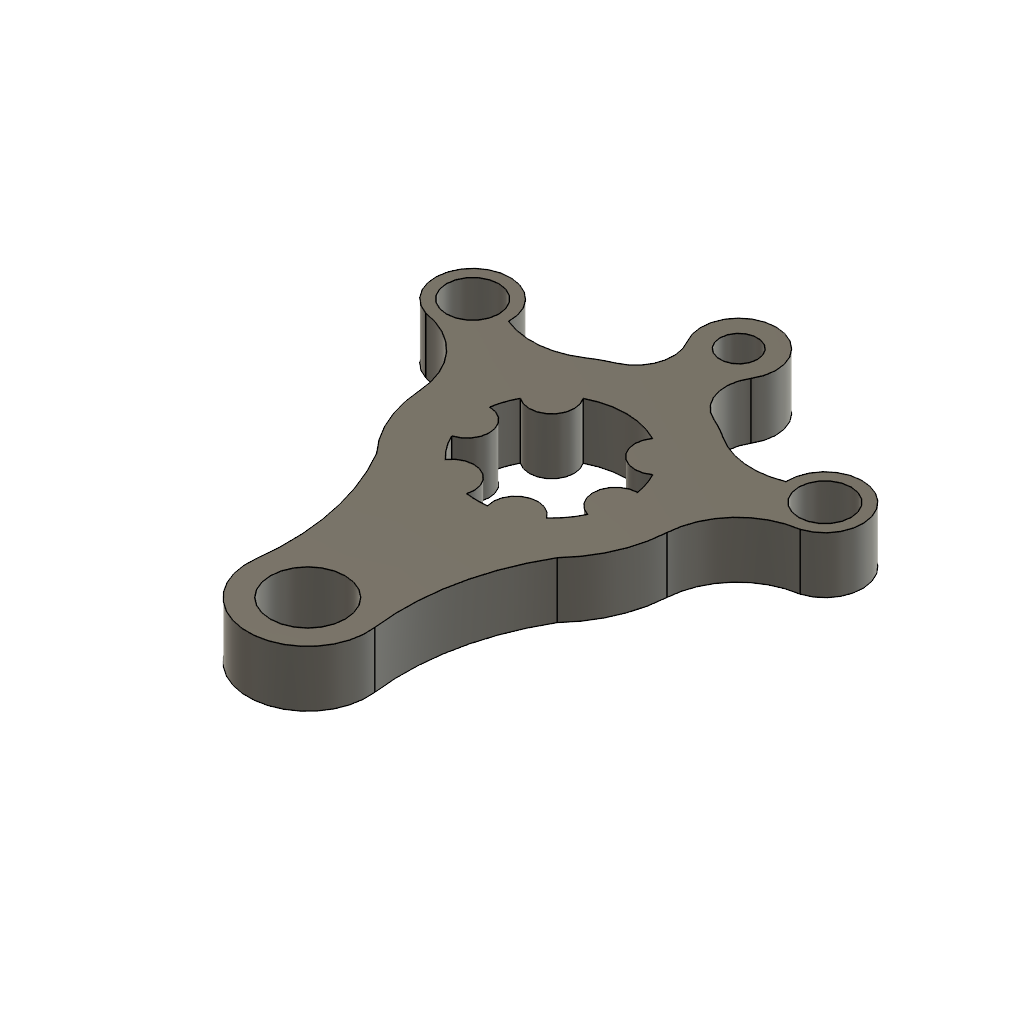
ex 1.1 (Autodesk Fusion 360 design; units mm, degrees)
part number: 2026-10-05-16-02-38-002
Autodesk Fusion 360 part; units mm, degrees
sketch "Sketch1" plane through (0, 0, 0) normal (0, 1, 0) x (1, 0, 0)
  line L0 (0, 0) -> (0, -65)
  line L1 (0, 0) -> (0, 50)
  line L2 (0, 50) -> (-47, 50)
  circle A0 centre (-47, 26) radius 7
  circle A1 centre (0, -65) radius 10
  circle A2 centre (0, 50) radius 5
  arc A3 (-13.0587, 30.3063) -> (-9.5135, 46.1017) centre (-17.0159, 39.49) ccw
  arc A4 (-37.0085, 25.5888) -> (-18.3132, 27.4523) centre (-29.4121, 44.09) ccw
  arc A5 (-9.5135, 46.1017) -> (-10.3052, 50) centre (-29.4121, 44.09) ccw
  arc A6 (-13.0587, 30.3063) -> (-18.3132, 27.4523) centre (0, 0) ccw
  arc A7 (-2.778, -19.8061) -> (-13.5097, -14.7474) centre (-8.5276, -18.0909) ccw
  arc A8 (-18.1189, -8.4679) -> (-13.5097, -14.7474) centre (0, 0) ccw
  arc A9 (-18.1189, -8.4679) -> (-19.7281, 3.2867) centre (-19.8152, -2.7127) ccw
  arc A10 (-17.6648, 9.3783) -> (-19.7281, 3.2867) centre (0, 0) ccw
  arc A11 (-17.6648, 9.3783) -> (-9.2437, 17.7357) centre (-14.0883, 14.1958) ccw
  arc A12 (-32.9346, -2.0764) -> (-49.9628, 16.449) centre (-52.895, -3.3349) ccw
  arc A13 (-15.8705, -62.9687) -> (-24.1042, -22.5385) centre (-79.3527, -54.8435) ccw
  circle A14 centre (0, -65) radius 10
  arc A15 (24.1042, -22.5385) -> (15.8705, -62.9687) centre (79.3527, -54.8435) ccw
  arc A16 (19.7281, 3.2867) -> (18.1189, -8.4679) centre (19.8152, -2.7127) ccw
  arc A17 (13.5097, -14.7474) -> (18.1189, -8.4679) centre (0, 0) ccw
  arc A18 (9.2437, 17.7357) -> (17.6648, 9.3783) centre (14.0883, 14.1958) ccw
  arc A19 (9.5135, 46.1017) -> (13.0587, 30.3063) centre (17.0159, 39.49) ccw
  arc A20 (18.3132, 27.4523) -> (13.0587, 30.3063) centre (0, 0) ccw
  arc A21 (18.3132, 27.4523) -> (37.0085, 25.5888) centre (29.4121, 44.09) ccw
  circle A22 centre (47, 26) radius 7
  arc A23 (49.9628, 16.449) -> (32.9346, -2.0764) centre (52.895, -3.3349) ccw
  arc A24 (-15.8705, -62.9687) -> (15.8705, -62.9687) centre (0, -65) ccw
  arc A25 (-15.8705, -62.9687) -> (15.8705, -62.9687) centre (0, -65) ccw
  arc A26 (8.5079, 44.745) -> (-8.5079, 44.745) centre (0, 50) ccw
  arc A27 (47.9568, 16.0459) -> (37.0085, 25.5888) centre (47, 26) ccw
  arc A28 (-37.0085, 25.5888) -> (-47.9568, 16.0459) centre (-47, 26) ccw
  arc A29 (13.5097, -14.7474) -> (2.778, -19.8061) centre (8.5276, -18.0909) ccw
  line L3 (0, 0) -> (0, -65)
  arc A30 (-2.778, -19.8061) -> (2.778, -19.8061) centre (0, 0) ccw
  arc A31 (-2.778, -19.8061) -> (2.778, -19.8061) centre (0, 0) ccw
  arc A32 (13.5097, -14.7474) -> (18.1189, -8.4679) centre (0, 0) ccw
  arc A33 (19.7281, 3.2867) -> (17.6648, 9.3783) centre (0, 0) ccw
  arc A34 (9.2437, 17.7357) -> (-9.2437, 17.7357) centre (0, 0) ccw
  arc A35 (9.2437, 17.7357) -> (-9.2437, 17.7357) centre (0, 0) ccw
  arc A36 (-17.6648, 9.3783) -> (-19.7281, 3.2867) centre (0, 0) ccw
  arc A37 (-18.1189, -8.4679) -> (-13.5097, -14.7474) centre (0, 0) ccw
  arc A38 (8.5079, 44.745) -> (-8.5079, 44.745) centre (0, 50) ccw
  arc A39 (29.6039, -14.5811) -> (32.9346, -2.0764) centre (0, 0) ccw
  arc A40 (-32.9346, -2.0764) -> (-24.1042, -22.5385) centre (0, 0) ccw
  arc A41 (24.1042, -22.5385) -> (32.9346, -2.0764) centre (0, 0) ccw
  arc A42 (18.3132, 27.4523) -> (13.0587, 30.3063) centre (0, 0) ccw
  arc A43 (-13.0587, 30.3063) -> (-18.3132, 27.4523) centre (0, 0) ccw
  arc A44 (-32.9346, -2.0764) -> (-24.1042, -22.5385) centre (0, 0) ccw
  dimension "d1" = 40
  dimension "d2" = 65
  dimension "d3" = 47
  dimension "d4" = 24
  dimension "d5" = 14
  dimension "d6" = 20
  dimension "d7" = 20
  dimension "d8" = 32
  dimension "d9" = 10
  dimension "d10" = 20
  dimension "d11" = 66
  dimension "d12" = 128
  dimension "d13" = 40
  dimension "d14" = 40
  dimension "d15" = 20
  dimension "d16" = 12
  dimension "d17" = 12
  dimension "d18" = 12
  constraint coincident L0.start L1.start
  constraint vertical L0
  constraint parallel L0 L1
  constraint perpendicular L1 L2
  constraint concentric A0 A28
  constraint coincident L0.end A1.centre
  constraint concentric A1 A24
  constraint coincident L1.end L2.start
  constraint concentric A2 A26
  constraint concentric A6 A34
  constraint tangent A12 A40
  constraint tangent A5 A26
  constraint tangent A4 A6
  constraint tangent A3 A26
  constraint tangent A3 A6
  constraint coincident L2 A5.end
  constraint concentric A4 A5
  constraint concentric A6 A42
  constraint coincident A7.centre A31
  constraint coincident A9.centre A10
  constraint coincident A11.centre A34
  constraint concentric A8 A31
  constraint concentric A10 A34
  constraint tangent A13 A24
  constraint coincident A12.end A28
  constraint symmetric L1 A0 A22
  constraint symmetric L1 A27 A28
  constraint symmetric L1 A1 A14
  constraint symmetric L1 A24 A25
  constraint symmetric L1 A26 A38
  constraint symmetric L1 A3.end A19.start
  constraint symmetric L1 A3 A19
  constraint symmetric L1 A4.end A20.start
  constraint symmetric L1 A4 A21
  constraint symmetric L1 A3.start A19.end
  constraint symmetric L1 A12.start A23.end
  constraint symmetric L1 A6 A20
  constraint symmetric L1 A42 A43
  constraint symmetric L1 A7.end A17.start
  constraint symmetric L1 A7.start A29.end
  constraint symmetric L1 A9.end A16.start
  constraint symmetric L1 A8.start A16.end
  constraint symmetric L1 A8 A17
  constraint symmetric L1 A9 A16
  constraint symmetric L1 A11.end A18.start
  constraint symmetric L1 A10.start A18.end
  constraint symmetric L1 A34 A35
  constraint symmetric L1 A11 A18
  constraint symmetric L1 A12 A23
  constraint symmetric L1 A13 A15
  constraint symmetric L1 A13.start A15.end
  constraint symmetric L1 A12.end A23.start
  constraint coincident A3 A26.end
  constraint coincident A19 A26.start
  constraint coincident A23 A27.start
  constraint coincident A12 A28.end
  constraint symmetric L1.start L0 A6.centre
  constraint symmetric A1.centre L0 A14.centre
  constraint symmetric L0 A7.end A17.start
  constraint symmetric L0 A7.start A29.end
  constraint symmetric L0 A7 A29
  constraint concentric A30 A37
  constraint concentric A32 A33
  constraint concentric A31 A32
  constraint concentric A33 A34
  constraint concentric A35 A36
  constraint concentric A36 A37
  constraint concentric A40 A42
  constraint concentric A41 A42
  constraint concentric A43 A44
  measures "d1" diameter of A31
  measures "d2" distance of L0.start L0.end
  measures "d3" distance of L1.end L2.end
  measures "d4" distance of L2.end A0.centre
  measures "d5" diameter of A0
  measures "d6" diameter of A28
  measures "d7" diameter of A1
  measures "d8" diameter of A24
  measures "d9" diameter of A2
  measures "d10" diameter of A26
  measures "d11" diameter of A6
  measures "d12" diameter of A13
  measures "d13" diameter of A12
  measures "d14" diameter of A4
  measures "d15" diameter of A3
  measures "d16" diameter of A7
  measures "d17" diameter of A9
  measures "d18" diameter of A11
extrude "Extrude1" add sketch "Sketch1" along normal blind 15 contours A3 A4 A6 A12 A13 A15 A19 A20 A21 A23 A24 A25 A26 A27 A28 A38 A39 A40 A41 A42 A43 A44
